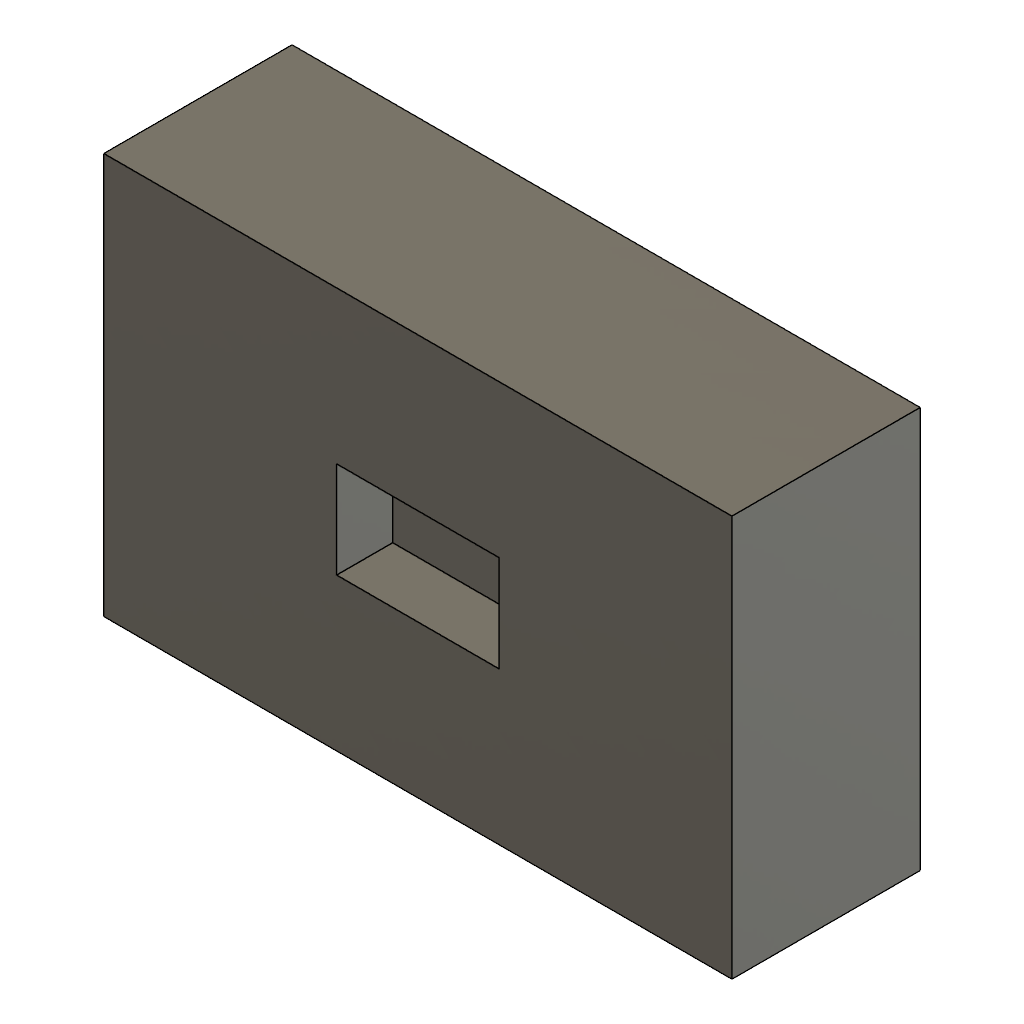
CutTrain (Autodesk Fusion 360 design; units mm, degrees)
part number: 2026-11-23-18-10-15-059
Autodesk Fusion 360 part; units mm, degrees
sketch "RectangleSketch" plane through (0, 0, 0) normal (0, 0, 1) x (1, 0, 0)
  line L0 (0, 0) -> (43.7, 0)
  line L1 (43.7, 0) -> (43.7, 27.9)
  line L2 (43.7, 27.9) -> (0, 27.9)
  line L3 (0, 27.9) -> (0, 0)
  dimension "width_mm" = 43.7
  dimension "height_mm" = 27.9
  constraint horizontal L0
  constraint vertical L1
  constraint horizontal L2
  constraint vertical L3
  constraint coincident L0.start L3.end
  measures "width_mm" horizontal distance of L0.start L0.end
  measures "height_mm" vertical distance of L0.start L2.end
extrude "BlindBoss" add sketch "RectangleSketch" along normal blind 13.1
sketch "CutSketch" plane through (0, 0, 13.1) normal (0, 0, 1) x (1, 0, 0)
  line L0 (0, 27.9) -> (0, 0)
  line L1 (0, 0) -> (43.7, 0)
  line L2 (43.7, 0) -> (43.7, 27.9)
  line L3 (43.7, 27.9) -> (0, 27.9)
  line L4 (16.2, 10.6) -> (27.5, 10.6)
  line L5 (27.5, 10.6) -> (27.5, 17.3)
  line L6 (27.5, 17.3) -> (16.2, 17.3)
  line L7 (16.2, 17.3) -> (16.2, 10.6)
  line L8 (16.2, 10.6) -> (27.5, 17.3) construction
  point P0 (21.85, 13.95)
  dimension "cut_width_mm" = 11.3
  dimension "cut_height_mm" = 6.7
  dimension "cut_center_u_mm" = 21.85
  dimension "cut_center_v_mm" = 13.95
  constraint horizontal L4
  constraint vertical L5
  constraint horizontal L6
  constraint vertical L7
  constraint midpoint L8 P0
  measures "cut_width_mm" horizontal distance of L4.start L4.end
  measures "cut_height_mm" vertical distance of L4.start L6.end
  measures "cut_center_u_mm" horizontal distance of P0 L0.end
  measures "cut_center_v_mm" vertical distance of P0 L0.end
extrude "BlindCut" cut sketch "CutSketch" against normal blind 3.9 contours L4 L5 L6 L7
equation "depth_mm = 13.1 mm"
equation "cut_center_u_mm = width_mm / 2"
equation "cut_center_v_mm = height_mm / 2"
equation "cut_depth_mm = -3.8999999999999999 mm"
